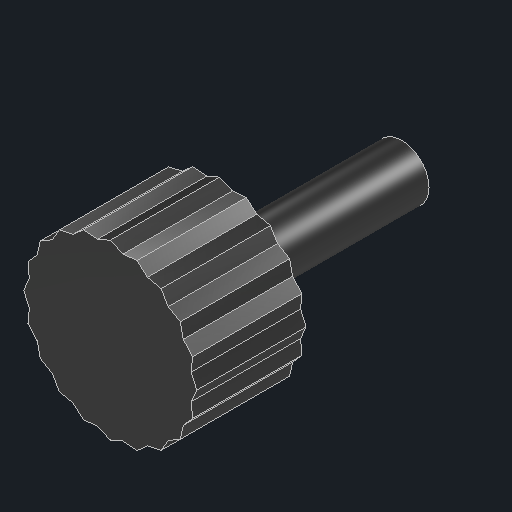
# Autodesk Inventor part: azimuth_knob
Saved by Autodesk Inventor 2027.1 (Build 311270010, 270A)
## iProperties
Created: 2026-11-04
Part Number: azimuth_knob
Material: Generic
Description: Azimuth adjustment knob
Document SubType Name: Modeling
Designer: Claude (from photos)
Density: 1 g/cm^3
Appearance: Glossy - Black
Author: alexg
Autodesk Inventor part; units mm, degrees
ref_plane "YZ Plane" through (0, 0, 0) normal (1, 0, 0) x (0, 1, 0)
ref_plane "XZ Plane" through (0, 0, 0) normal (0, 1, 0) x (-1, 0, 0)
sketch "Bolt M6 sketch" plane through (0, 0, 0) normal (0, 0, 1) x (1, 0, 0)
  circle A0 centre (0, 0) radius 3
  constraints: 1 centre point
extrude "Bolt M6" add sketch "Bolt M6 sketch" along normal blind 30
ref_plane "Work Plane1" through (0, 0, 20) normal (0, 0, 1) x (1, 0, 0)
sketch "Knurled knob sketch" plane through (0, 0, 20) normal (0, 0, 1) x (1, 0, 0)
  line L0 (9.5, 0) -> (8.8892, 1.4079)
  line L1 (8.8892, 1.4079) -> (9.035, 2.9357)
  line L2 (9.035, 2.9357) -> (8.0191, 4.0859)
  line L3 (8.0191, 4.0859) -> (7.6857, 5.584)
  line L4 (7.6857, 5.584) -> (6.364, 6.364)
  line L5 (6.364, 6.364) -> (5.584, 7.6857)
  line L6 (5.584, 7.6857) -> (4.0859, 8.0191)
  line L7 (4.0859, 8.0191) -> (2.9357, 9.035)
  line L8 (2.9357, 9.035) -> (1.4079, 8.8892)
  line L9 (1.4079, 8.8892) -> (0, 9.5)
  line L10 (0, 9.5) -> (-1.4079, 8.8892)
  line L11 (-1.4079, 8.8892) -> (-2.9357, 9.035)
  line L12 (-2.9357, 9.035) -> (-4.0859, 8.0191)
  line L13 (-4.0859, 8.0191) -> (-5.584, 7.6857)
  line L14 (-5.584, 7.6857) -> (-6.364, 6.364)
  line L15 (-6.364, 6.364) -> (-7.6857, 5.584)
  line L16 (-7.6857, 5.584) -> (-8.0191, 4.0859)
  line L17 (-8.0191, 4.0859) -> (-9.035, 2.9357)
  line L18 (-9.035, 2.9357) -> (-8.8892, 1.4079)
  line L19 (-8.8892, 1.4079) -> (-9.5, 0)
  line L20 (-9.5, 0) -> (-8.8892, -1.4079)
  line L21 (-8.8892, -1.4079) -> (-9.035, -2.9357)
  line L22 (-9.035, -2.9357) -> (-8.0191, -4.0859)
  line L23 (-8.0191, -4.0859) -> (-7.6857, -5.584)
  line L24 (-7.6857, -5.584) -> (-6.364, -6.364)
  line L25 (-6.364, -6.364) -> (-5.584, -7.6857)
  line L26 (-5.584, -7.6857) -> (-4.0859, -8.0191)
  line L27 (-4.0859, -8.0191) -> (-2.9357, -9.035)
  line L28 (-2.9357, -9.035) -> (-1.4079, -8.8892)
  line L29 (-1.4079, -8.8892) -> (0, -9.5)
  line L30 (0, -9.5) -> (1.4079, -8.8892)
  line L31 (1.4079, -8.8892) -> (2.9357, -9.035)
  line L32 (2.9357, -9.035) -> (4.0859, -8.0191)
  line L33 (4.0859, -8.0191) -> (5.584, -7.6857)
  line L34 (5.584, -7.6857) -> (6.364, -6.364)
  line L35 (6.364, -6.364) -> (7.6857, -5.584)
  line L36 (7.6857, -5.584) -> (8.0191, -4.0859)
  line L37 (8.0191, -4.0859) -> (9.035, -2.9357)
  line L38 (9.035, -2.9357) -> (8.8892, -1.4079)
  line L39 (8.8892, -1.4079) -> (9.5, 0)
  constraints: 80 end point
extrude "Knurled knob" add sketch "Knurled knob sketch" along normal blind 12
body "Solid1"
